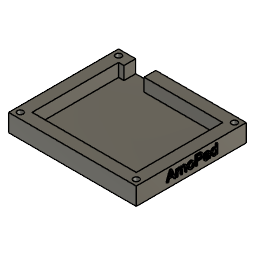
ArnoPad case and lid (Autodesk Fusion 360 archive; units mm, degrees)
design "ArnoPad case"
part number: 2026-09-11-17-03-47-557
Autodesk Fusion 360 part; units mm, degrees
derive "DerivedContext1"
sketch "Sketch1" plane through (0, 0, 0) normal (0, 0, 1) x (1, 0, 0)
  line L0 (35, -30) -> (-53.4, -30)
  line L1 (-53.4, -30) -> (-53.4, 43.4)
  line L2 (-53.4, 43.4) -> (35, 43.4)
  line L3 (35, 43.4) -> (35, -30)
  line L4 (35, -30) -> (45, -30)
  line L5 (45, -30) -> (45, -40)
  line L6 (45, -40) -> (35, -40)
  line L7 (35, -40) -> (35, -30)
  line L8 (35, 43.4) -> (45, 43.4)
  line L9 (45, 43.4) -> (45, 53.4)
  line L10 (45, 53.4) -> (35, 53.4)
  line L11 (35, 53.4) -> (35, 43.4)
  line L12 (-53.4, -30) -> (-63.4, -30)
  line L13 (-63.4, -30) -> (-63.4, -40)
  line L14 (-63.4, -40) -> (-53.4, -40)
  line L15 (-53.4, -40) -> (-53.4, -30)
  line L16 (-53.4, 43.4) -> (-63.4, 43.4)
  line L17 (-63.4, 43.4) -> (-63.4, 53.4)
  line L18 (-63.4, 53.4) -> (-53.4, 53.4)
  line L19 (-53.4, 53.4) -> (-53.4, 43.4)
  line L20 (45, -40) -> (-63.4, -40)
  line L21 (-63.4, -40) -> (-63.4, 53.4)
  line L22 (-63.4, 53.4) -> (45, 53.4)
  line L23 (45, 53.4) -> (45, -40)
  line L24 (-63.4, 53.4) -> (-53.4, 43.4)
  circle A0 centre (-58.4, 48.4) radius 2.5
  line L25 (-63.4, -30) -> (-53.4, -40)
  circle A1 centre (-58.4, -35) radius 2.5
  line L26 (35, -30) -> (45, -40)
  circle A2 centre (40, -35) radius 2.5
  line L27 (35, 53.4) -> (45, 43.4)
  circle A3 centre (40, 48.4) radius 2.5
  dimension "d1" = 88.4
  dimension "d2" = 73.4
  dimension "d3" = 10
  dimension "d4" = 10
  dimension "d5" = 10
  dimension "d6" = 10
  dimension "d7" = 10
  dimension "d8" = 10
  dimension "d9" = 10
  dimension "d10" = 10
  dimension "d11" = 5
  dimension "d12" = 5
  dimension "d13" = 5
  dimension "d14" = 5
  constraint horizontal L0
  constraint vertical L1
  constraint horizontal L2
  constraint vertical L3
  constraint horizontal L4
  constraint vertical L5
  constraint horizontal L6
  constraint vertical L7
  constraint horizontal L8
  constraint vertical L9
  constraint horizontal L10
  constraint vertical L11
  constraint horizontal L12
  constraint vertical L13
  constraint horizontal L14
  constraint vertical L15
  constraint horizontal L16
  constraint vertical L17
  constraint horizontal L18
  constraint vertical L19
  constraint horizontal L20
  constraint vertical L21
  constraint horizontal L22
  constraint vertical L23
  constraint midpoint L24 A0.centre
  constraint midpoint L25 A1.centre
  constraint midpoint L26 A2.centre
  constraint midpoint L27 A3.centre
  measures "d1" distance of L0.start L0.end
  measures "d2" distance of L0.start L2.end
  measures "d3" distance of L0.start L4.end
  measures "d4" distance of L0.start L6.end
  measures "d5" distance of L2.end L8.end
  measures "d6" distance of L2.end L10.end
  measures "d7" distance of L0.end L12.end
  measures "d8" distance of L0.end L14.end
  measures "d9" distance of L1.end L16.end
  measures "d10" distance of L1.end L18.end
  measures "d11" diameter of A0
  measures "d12" diameter of A1
  measures "d13" diameter of A2
  measures "d14" diameter of A3
extrude "Extrude1" add sketch "Sketch1" along normal blind 4 contours L0 L7 L15 L20 | L0 L1 L2 L3 | L3 L4 L8 L23 | L6 L7 L20 L26 A2 | L4 L5 L23 L26 A2 | L1 L12 L16 L21 | L12 L15 L25 A1 | L8 L11 L27 A3 | L2 L11 L19 L22 | L18 L19 L22 L24 A0 | L16 L17 L21 L24 A0 | L13 L14 L20 L21 L25 A1 | L9 L10 L22 L23 L27 A3
sketch "Sketch2" plane through (0, 0, 4) normal (0, 0, 1) x (-1, 0, 0)
  circle A0 centre (58.4, -48.4) radius 2.5
  circle A1 centre (-40, -48.4) radius 2.5
  circle A2 centre (58.4, 35) radius 2.5
  circle A3 centre (-40, 35) radius 2.5
  line L0 (-45, -53.4) -> (63.4, -53.4)
  line L1 (63.4, -53.4) -> (63.4, 40)
  line L2 (63.4, 40) -> (-45, 40)
  line L3 (-45, 40) -> (-45, -53.4)
  line L4 (63.4, -53.4) -> (53.4, -53.4)
  line L5 (53.4, -53.4) -> (53.4, -43.4)
  line L6 (53.4, -43.4) -> (63.4, -43.4)
  line L7 (63.4, -43.4) -> (63.4, -53.4)
  line L8 (-45, 40) -> (-35, 40)
  line L9 (-35, 40) -> (-35, 30)
  line L10 (-35, 30) -> (-45, 30)
  line L11 (-45, 30) -> (-45, 40)
  line L12 (53.4, -43.4) -> (-35, -43.4)
  line L13 (-35, -43.4) -> (-35, 30)
  line L14 (-35, 30) -> (53.4, 30)
  line L15 (53.4, 30) -> (53.4, -43.4)
  line L16 (63.4, 40) -> (-45, 40)
  line L17 (-45, 40) -> (-45, -53.4)
  line L18 (-45, -53.4) -> (63.4, -53.4)
  line L19 (63.4, -53.4) -> (63.4, 40)
  line L20 (53.4, 30) -> (63.4, 30)
  line L21 (63.4, 30) -> (63.4, 40)
  line L22 (63.4, 40) -> (53.4, 40)
  line L23 (53.4, 40) -> (53.4, 30)
  line L24 (-35, -43.4) -> (-45, -43.4)
  line L25 (-45, -43.4) -> (-45, -53.4)
  line L26 (-45, -53.4) -> (-35, -53.4)
  line L27 (-35, -53.4) -> (-35, -43.4)
  line L28 (63.4, -53.4) -> (53.4, -43.4)
  line L29 (-35, -43.4) -> (-45, -53.4)
  line L30 (-35, 30) -> (-45, 40)
  line L31 (63.4, 40) -> (53.4, 30)
  circle A4 centre (58.4, -48.4) radius 2.5
  circle A5 centre (58.4, 35) radius 2.5
  circle A6 centre (-40, -48.4) radius 2.5
  circle A7 centre (-40, 35) radius 2.5
  dimension "d17" = 10
  dimension "d18" = 10
  dimension "d19" = 10
  dimension "d20" = 10
  dimension "d21" = 5
  dimension "d22" = 5
  dimension "d23" = 5
  dimension "d24" = 5
  constraint horizontal L4
  constraint vertical L5
  constraint horizontal L6
  constraint vertical L7
  constraint coincident L0.end L1.start
  constraint horizontal L8
  constraint vertical L9
  constraint horizontal L10
  constraint vertical L11
  constraint coincident L2.end L3.start
  constraint horizontal L12
  constraint vertical L13
  constraint horizontal L14
  constraint vertical L15
  constraint horizontal L16
  constraint vertical L17
  constraint horizontal L18
  constraint vertical L19
  constraint coincident L0.start L3.end
  constraint coincident L1.end L2.start
  constraint horizontal L20
  constraint vertical L21
  constraint horizontal L22
  constraint vertical L23
  constraint horizontal L24
  constraint vertical L25
  constraint horizontal L26
  constraint vertical L27
  constraint concentric A0 A4
  constraint concentric A2 A5
  constraint concentric A1 A6
  constraint concentric A3 A7
  measures "d17" distance of L0.end L4.end
  measures "d18" distance of L0.end L6.end
  measures "d19" distance of L2.end L8.end
  measures "d20" distance of L2.end L10.end
  measures "d21" diameter of A4
  measures "d22" diameter of A5
  measures "d23" diameter of A6
  measures "d24" diameter of A7
extrude "Extrude2" add sketch "Sketch2" along normal blind 11 contours A0 L1 L6 L7 L19 L28 A4 | A0 L0 L4 L5 L18 L28 A4 | L1 L6 L15 L19 L20 | L0 L5 L12 L18 L27 | L3 L10 L13 L17 L24 | A1 L3 L17 L24 L25 L29 A6 | A1 L0 L18 L26 L27 L29 A6 | A2 L1 L19 L20 L21 L31 A5 | L2 L9 L14 L16 L23 | A2 L2 L16 L22 L23 L31 A5 | A3 L2 L8 L9 L16 L30 A7 | A3 L3 L10 L11 L17 L30 A7
sketch "Sketch3" plane through (0, 0, 0) normal (0, 0, 1) x (1, 0, 0)
sketch "sketch 2586" plane through (78.1684, 53.4, 0) normal (0, 1, 0) x (-1, 0, 0)
  line L0 (33.1684, 0) -> (141.5684, 0)
  line L1 (141.5684, 0) -> (141.5684, 15)
  line L2 (141.5684, 15) -> (33.1684, 15)
  line L3 (33.1684, 15) -> (33.1684, 0)
  line L4 (110, 15) -> (127, 15)
  line L5 (127, 15) -> (127, 0)
  line L6 (127, 0) -> (110, 0)
  line L7 (110, 0) -> (110, 15)
  line L8 (110, 2) -> (127, 2)
  line L9 (127, 2) -> (127, 12)
  line L10 (127, 12) -> (110, 12)
  line L11 (110, 12) -> (110, 2)
  line L12 (110, 12) -> (127, 12)
  line L13 (127, 12) -> (127, 4)
  line L14 (127, 4) -> (110, 4)
  line L15 (110, 4) -> (110, 12)
  line L16 (127, 12) -> (127, 4)
  line L17 (127, 4) -> (110, 4)
  line L18 (110, 4) -> (110, 12)
  line L19 (110, 12) -> (127, 12)
extrude "Extrude3" cut sketch "sketch 2586" against normal blind 45 contours L5 L7 L9 L10 L11 L12 L13 L14 L15 L16 L17 L18 L19
sketch "Sketch4" plane through (45, 0, 0) normal (1, 0, 0) x (0, 1, 0)
  line L0 (-40, 0) -> (53.4, 0)
  line L1 (53.4, 0) -> (53.4, 15)
  line L2 (53.4, 15) -> (-40, 15)
  line L3 (-40, 15) -> (-40, 0)
  line L4 (-25, 5) -> (38.3935, 5) construction
  line L5 (38.3935, 5) -> (38.3935, 12.9787) construction
  line L6 (38.3935, 12.9787) -> (-25, 12.9787) construction
  line L7 (-25, 12.9787) -> (-25, 5) construction
  dimension "d29" = 8
  text T0 "ArnoPad" font "Arial" height 8 align centre middle in box 63.3935 x 7.9787 at (-25, 5) x (1, 0) y (0, 1) spacing 1.005 kerned
emboss "Emboss1" depth 1 profiles "Sketch4" section 1 text T0 onto face at (45, -8.8667, 5)
sketch "Sketch5" plane through (0, 53.4, 0) normal (0, 1, 0) x (-1, 0, 0)
  line L0 (48.8316, 12) -> (48.8316, 4)
  line L1 (48.8316, 4) -> (31.8316, 4)
  line L2 (31.8316, 4) -> (31.8316, 12)
  line L3 (31.8316, 12) -> (48.8316, 12)
  line L4 (-45, 0) -> (63.4, 0)
  line L5 (63.4, 0) -> (63.4, 15)
  line L6 (63.4, 15) -> (-45, 15)
  line L7 (-45, 15) -> (-45, 0)
  line L8 (48.8316, 12) -> (31.8316, 12)
  line L9 (31.8316, 12) -> (31.8316, 15)
  line L10 (31.8316, 15) -> (48.8316, 15)
  line L11 (48.8316, 15) -> (48.8316, 12)
  constraint horizontal L8
  constraint vertical L9
  constraint horizontal L10
  constraint vertical L11
  constraint coincident L6 L9.end
  constraint coincident L0.start L3.end
extrude "Extrude4" cut sketch "Sketch5" against normal blind 39 contours L3 L6 L8 L9 L10 L11
equation "d30 = 'ArnoPad'"
